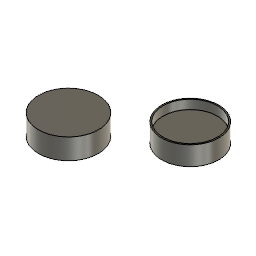
CR2032 (Autodesk Fusion 360 design; units mm, degrees)
part number: 2026-05-05-20-24-02-289
Autodesk Fusion 360 part; units mm, degrees
sketch "Sketch1" plane through (0, 0, 0) normal (0, 0, 1) x (1, 0, 0)
cylinder "CylinderPrimitive1" add diameter 20 height 3.6 placed x (1, 0, 0) y (0, 1, 0) z (0, 0, 1) at (0, 0.2955, 0) makes body 1
sketch "Sketch3" plane through (0, 0, 0) normal (0, 0, 1) x (1, 0, 0)
cylinder "CylinderPrimitive3" add diameter 21 height 7 placed x (1, 0, 0) y (0, 1, 0) z (0, 0, 1) at (-23.4166, -21.0308, 0) separate body makes body 2
cylinder "CylinderPrimitive4" add diameter 22 height 7.6 placed x (1, 0, 0) y (0, 1, 0) z (0, 0, 1) at (-27.0196, 13.7363, 0) separate body makes body 3
move_face "MoveFace1" to x (1, 0, 0) y (0, 1, 0) z (0, 0, 1) at (-1.5495, 0.0826, -1.2727) 1 faces at (-16.0332, 13.188, 5.0667) on bodies 3
move_body "Align1" bodies 3 to x (1, 0, 0) y (0, 1, 0) z (0, 0, 1) at (5.1526, -34.8498, 3.5)
move_body "Move1" bodies 3 to x (1, 0, 0) y (0, 1, 0) z (0, 0, 1) at (0, 0, -4)
copy_body "CopyPasteBodies1" bodies 2 makes body 4
move_body "Move2" bodies 4 to x (1, 0, 0) y (0, 1, 0) z (0, 0, 1) at (0, 0, 28)
move_body "Move3" bodies 2 to x (1, 0, 0) y (0, 1, 0) z (0, 0, 1) at (0, 0, -1)
combine "Combine1" operation cut target body 3 tool bodies 2
move_body "Align2" bodies 4 to x (1, 0, 0) y (0, 1, 0) z (0, 0, 1) at (23.4166, 21.3264, -29.7)
move_body "Move4" bodies 1 to x (1, 0, 0) y (0, 1, 0) z (0, 0, 1) at (0, 0, 2)
combine "Combine2" operation cut target body 4 tool bodies 1
